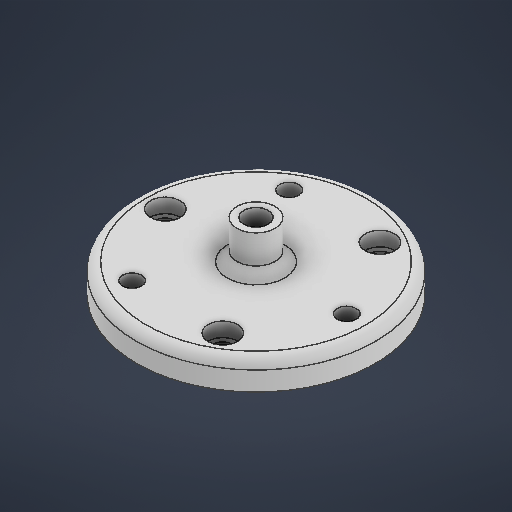
# Autodesk Inventor part: roter
Saved by Autodesk Inventor 2026.2 (Build 302298010, 298A)
## iProperties
Created: 2026-03-31
Part Number: roter
Material: 일반
Document SubType Name: Modeling
Designer: work
Density: 1 g/cm^3
Appearance: 기본값
Author: work
Autodesk Inventor part; units mm, degrees
ref_plane "YZ Plane" through (0, 0, 0) normal (1, 0, 0) x (0, 1, 0)
ref_plane "XZ Plane" through (0, 0, 0) normal (0, 1, 0) x (-1, 0, 0)
ref_plane "XY Plane" through (0, 0, 0) normal (0, 0, 1) x (1, 0, 0)
sketch "스케치1" plane through (0, 0, 0) normal (0, 1, 0) x (-1, 0, 0)
  circle A0 centre (0, 0) radius 19 construction
  line L0 (0, 0) -> (19, 0) construction
  circle A1 centre (19, 0) radius 2
  circle A2 centre (0, 0) radius 25
  circle A3 centre (0, 0) radius 2.55
  circle A4 centre (9.5, 16.4545) radius 2
  circle A5 centre (-9.5, 16.4545) radius 2
  circle A6 centre (-19, 0) radius 2
  circle A7 centre (-9.5, -16.4545) radius 2
  circle A8 centre (9.5, -16.4545) radius 2
  dimension "d0" = 38
  dimension "d1" = 4
  dimension "d2" = 50
  dimension "d3" = 5.1
  dimension "d15" = 360
  constraints: 8 centre point, 4 coincident, 2 end point, 1 horizontal, 1 horizontal alignment, 15 other
  measures "d1" diameter of A1
  measures "d2" diameter of A2
  measures "d3" diameter of A3
extrude "돌출1" add sketch "스케치1" along normal blind 6
sketch "스케치2" plane through (0, 6, 0) normal (0, 1, 0) x (1, 0, 0)
  circle A0 centre (-19, 0) radius 2 projected
  point P0 (0, 0)
  constraints: 1 coincident
hole "구멍1" at (-19, 6, 0) direction (0, -1, 0) diameter 4 end through all counterbore diameter 6.2 counterbore depth 3
pattern_circular "원형 패턴1" count 3 over 360 about axis through (0, 0, 0) along (0, 1, 0) of "구멍1"
sketch "스케치3" plane through (0, 0, 0) normal (0, 0, 1) x (1, 0, 0)
  circle A0 centre (0, 3) radius 1.6
  line L0 (-2.55, 6) -> (2.55, 6) projected
  point P0 (0, 0)
  dimension "d20" = 3.2
  dimension "d21" = 3
  constraints: 1 centre point
  measures "d20" diameter of A0
  measures "d21" distance from line of L0 A0.centre
extrude "돌출2" cut sketch "스케치3" against normal through all
sketch "스케치4" plane through (0, 6, 0) normal (0, 1, 0) x (1, 0, 0)
  circle A0 centre (0, 0) radius 4
  circle A1 centre (9.5, 16.4545) radius 3.1 projected
  circle A2 centre (9.5, -16.4545) radius 3.1 projected
  circle A3 centre (-19, 0) radius 3.1 projected
  circle A4 centre (0, 0) radius 25 projected
  circle A5 centre (-9.5, 16.4545) radius 2 projected
  circle A6 centre (19, 0) radius 2 projected
  circle A7 centre (-9.5, -16.4545) radius 2 projected
  circle A8 centre (0, 0) radius 2.55 projected
  dimension "d24" = 8
  constraints: 1 centre point, 1 coincident
  measures "d24" diameter of A0
extrude "돌출3" add sketch "스케치4" along normal blind 8 contours A0
chamfer "모따기1" distance 2 angle 45 1 edges at (-4, 6, 0)
fillet "모깎기1" radius 2 1 edges at (25, 6, 0)
